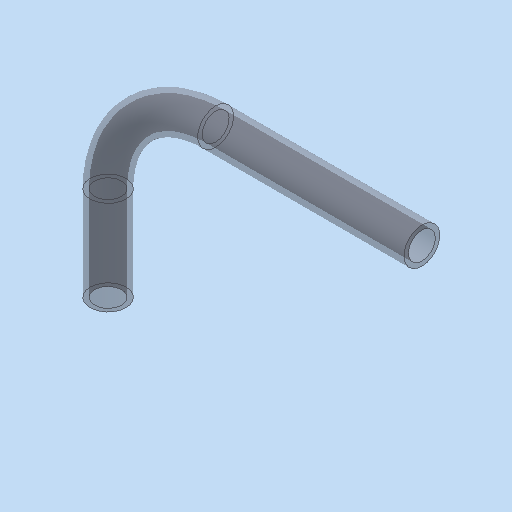
# Autodesk Inventor part: MM0870AN110_G04_515
Saved by Autodesk Inventor 2023.3 (Build 273359000, 359)
## iProperties
Part Number: MM0870AN110_G04_515
Material: Generisch
Description: =<RBPARTNOTITLE2>
Document SubType Name: Modeling
Designer: HH/Leu
Density: 1 g/cm^3
Appearance: grau - klar AnP
Vendor: Perma-Tech
Mass: 2.30245 g
Surface Area: 46.4889 cm^2
Volume: 2.30245 cm^3
RBDOCUMENTTYPE: DRF
RBDOCUMENTVERSION: 00
RBDRAWINGMAINSCALE: 1:1
RBDRAWINGMISSINGSPEC: --
RBDRAWINGVOLUME: --
RBGBEDGESIN1: +0,5
RBGBEDGESIN2: +0,2
RBGBEDGESOUT1: -0,3
RBGBEDGESOUT2: -0,1
RBMATERIAL: --
RBMATMEETS: --
RBMATNO: =<Part Number>
RBPARTMADEOF: 101393   (0,3m)
RBPARTNO: SIEHE MNR
RBPARTNOTITLE1: Hose up to +80 ° C aØ 8 mm x iØ 6 mm
RBPARTNOTITLE2: Schlauch bis +80 °C aØ 8 mm x iØ 6 mm
RBPARTSAFETYINDICATOR: --
RBSURFACE: --
RBSURFACE2: --
RBZEDGESNORM: ISO13715:2002-06
RBZGENDIMCLASS: m
RBZGENDIMNORM: ISO 2768-1:1989-11
RBZGENGEOCLASS: H
RBZGENGEONORM: ISO 2768-2:1989-11
RBZSURFACENORM: ISO13D2:2002-02
RBZTOLERANCENORM: ISO 14405-1:2010-12
RBGBREMARKSINDEX: E
AnP_Material: =<Material>
AnP_TemplVers: 20190222
AnP_Kategorie: 2
Author: HH/Leu
Keywords: =<RBPARTMADEOF>
Comments: =<RBSURFACE2>
Revision Number: 01
Autodesk Inventor part; units mm, degrees
ref_plane "YZ Plane" through (0, 0, 0) normal (1, 0, 0) x (0, 1, 0)
ref_plane "XZ Plane" through (0, 0, 0) normal (0, 1, 0) x (-1, 0, 0)
ref_plane "XY Plane" through (0, 0, 0) normal (0, 0, 1) x (1, 0, 0)
sketch "Skizze1" plane through (0, 0, 0) normal (0, 0, 1) x (1, 0, 0)
  circle A0 centre (0, 0) radius 4
  circle A1 centre (0, 0) radius 3
  dimension "d0" = 8
  dimension "d1" = 6
  constraints: 2 centre point, 2 coincident
  measures "d0" diameter of A0
  measures "d1" diameter of A1
sketch "Skizze2" plane through (0, 0, 0) normal (0, 1, 0) x (-1, 0, 0)
  line L0 (0, 0) -> (0, 21)
  arc A0 (0, 21) -> (-24, 45) centre (-24, 21) ccw
  line L1 (-24, 45) -> (-70, 45)
  line L2 (0, -9.9941) -> (0, 59.9647) construction
  line L3 (-84.9941, 0) -> (19.9647, 0) construction
  dimension "d2" = 45
  dimension "d3" = 24
  dimension "d6" = 70
  constraints: 4 end point, 2 point on circle, 2 tangent, 1 centre point, 1 perpendicular, 1 vertical
  measures "d2" distance between parallel lines of L3 L1
  measures "d3" radius of A0
  measures "d6" distance from line of L2 L1.end
sweep "Sweeping1" add profiles "Skizze1" path "Skizze2"
